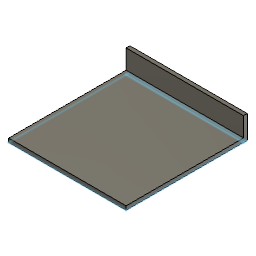
Edge_support_base_V1 (Autodesk Fusion 360 design; units mm, degrees)
part number: 2026-04-16-20-12-15-788
Autodesk Fusion 360 part; units mm, degrees
sketch "Sketch1" plane through (0, 0, 0) normal (0, 1, 0) x (1, 0, 0)
  line L0 (6.1025, -7.7455) -> (158.5025, -7.7455)
  line L1 (158.5025, -7.7455) -> (158.5025, -160.1455)
  line L2 (158.5025, -160.1455) -> (6.1025, -160.1455)
  line L3 (6.1025, -160.1455) -> (6.1025, -7.7455)
  line L4 (6.1025, -7.7455) -> (158.5025, -7.7455)
  line L5 (158.5025, -7.7455) -> (158.5025, -4.7455)
  line L6 (158.5025, -4.7455) -> (6.1025, -4.7455)
  line L7 (6.1025, -4.7455) -> (6.1025, -7.7455)
  dimension "d1" = 152.4
  dimension "d2" = 152.4
  dimension "d3" = 3
  constraint horizontal L0
  constraint vertical L1
  constraint horizontal L2
  constraint vertical L3
  constraint horizontal L4
  constraint vertical L5
  constraint horizontal L6
  constraint vertical L7
  measures "d1" distance of L0.start L0.end
  measures "d2" distance of L0.start L2.end
  measures "d3" distance of L0.start L6.end
extrude "Extrude1" add sketch "Sketch1" along normal blind 3 contours L0 L1 L2 L3 L4
extrude "Extrude2" add sketch "Sketch1" along normal blind 30 contours L0 L4 L5 L6 L7
extrude "Extrude3" add 1 faces at (107.7025, 3, 58.5455) along direction (0, 1, 0) blind 2
extrude "Extrude4" add 1 faces at (107.7025, 10, 4.7455) along direction (0, 0, -1) blind 2
